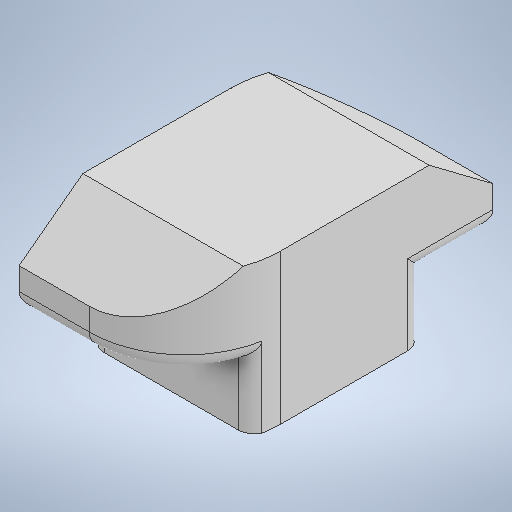
# Autodesk Inventor part: Agarrador_20x20
Saved by Autodesk Inventor 2025.3 (Build 293356030, 356C)
## iProperties
Created: 2026-05-06
Part Number: Agarrador_20x20
Material: Generic
Document SubType Name: Modeling
Designer: pablo
Density: 1 g/cm^3
Appearance: Default
Author: pablo
Autodesk Inventor part; units mm, degrees
ref_plane "YZ Plane" through (0, 0, 0) normal (1, 0, 0) x (0, 1, 0)
ref_plane "XZ Plane" through (0, 0, 0) normal (0, 1, 0) x (-1, 0, 0)
ref_plane "XY Plane" through (0, 0, 0) normal (0, 0, 1) x (1, 0, 0)
sketch "Sketch1" plane through (0, 0, 0) normal (0, 1, 0) x (-1, 0, 0)
  line L0 (0, 0) -> (5.2, 0)
  line L1 (5.2, 0) -> (5.2, -5.3)
  line L2 (5.2, -5.3) -> (0, -5.3)
  line L3 (0, -5.3) -> (0, 0)
  dimension "d0" = 5.3
  dimension "d1" = 5.2
  constraints: 8 end point, 2 parallel, 1 horizontal, 1 perpendicular
  measures "d0" distance of L2.end L0.start
  measures "d1" distance of L1.end L2.end
extrude "Extrusion1" add sketch "Sketch1" along normal blind 2
fillet "Fillet1" radius 0.5 4 edges at (0, 1, 0) (0, 1, -5.3) (-5.2, 1, 0) (-5.2, 1, -5.3)
sketch "Sketch3" plane through (0, 2, 0) normal (0, 1, 0) x (1, 0, 0)
  arc A0 (-4.7, 5.3) -> (-5.2, 4.8) centre (-4.7, 4.8) ccw projected
  line L0 (-5.2, 4.8) -> (-5.2, 0.5) projected
  arc A1 (-5.2, 0.5) -> (-4.7, 0) centre (-4.7, 0.5) ccw projected
  line L1 (-4.7, 0) -> (-0.5, 0) projected
  arc A2 (-0.5, 0) -> (0, 0.5) centre (-0.5, 0.5) ccw projected
  line L2 (0, 0.5) -> (0, 4.8) projected
  arc A3 (0, 4.8) -> (-0.5, 5.3) centre (-0.5, 4.8) ccw projected
  line L3 (-0.5, 5.3) -> (-4.7, 5.3) projected
  line L4 (0, -2.175) -> (-5.2, -2.175)
  line L5 (-5.2, -2.175) -> (-5.2, 7.475)
  line L6 (-5.2, 7.475) -> (0, 7.475)
  line L7 (0, 7.475) -> (0, -2.175)
  line L8 (-5.2, 4.8) -> (-5.2, 0.5) projected
  point P0 (0, 0)
  point P1 (-5.2, 2.65)
  point P2 (-5.2, 2.65)
  point P3 (0, 2.65)
  point P4 (0, 2.65)
  point P5 (-5.2, 2.65)
  dimension "d14" = 9.65
  constraints: 8 end point, 5 midpoint, 3 coincident, 2 parallel, 1 horizontal, 1 perpendicular
  measures "d14" distance of L4.end L5.end
extrude "Extrusion3" add sketch "Sketch3" along normal blind 2.7
chamfer "Chamfer2" distance 2 distance2 1.5 2 edges at (-2.6, 4.7, -7.475) (-2.6, 4.7, 2.175) measured on face at (-2.6, 4.7, -6.975) measured on face at (-2.6, 4.7, 1.675)
fillet "Fillet7" radius 3 2 edges at (-5.2, 2.6, -7.475) (0, 2.6, 2.175)
fillet "Fillet6" radius 0.5 4 edges at (0, 2, -6.1375) (-1.1, 2, -7.475) (-4.1, 2, 2.175) (-5.2, 2, 0.8375)
body "Solid1"
